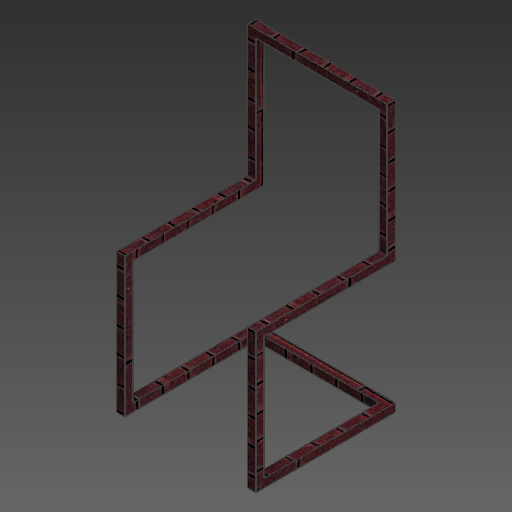
# Autodesk Inventor part: wednesday-23-09-2026
Saved by Autodesk Inventor 2026.1 (Build 301233020, 233B)
## iProperties
Created: 2026-09-23
Part Number: wednesday-23-09-2026
Material: Generic
Document SubType Name: Modeling
Designer: YmCris
Density: 1 g/cm^3
Appearance: Default
Author: YmCris
Autodesk Inventor part; units mm, degrees
ref_plane "YZ Plane" through (0, 0, 0) normal (1, 0, 0) x (0, 1, 0)
ref_plane "XZ Plane" through (0, 0, 0) normal (0, 1, 0) x (-1, 0, 0)
ref_plane "XY Plane" through (0, 0, 0) normal (0, 0, 1) x (1, 0, 0)
sketch "Sketch1" plane through (0, 0, 0) normal (0, 0, 1) x (1, 0, 0)
  line L0 (12.5, -12.5) -> (-12.5, -12.5)
  line L1 (-12.5, -12.5) -> (-12.5, 12.5)
  line L2 (-12.5, 12.5) -> (12.5, 12.5)
  line L3 (12.5, 12.5) -> (12.5, -12.5)
  dimension "d0" = 25
  dimension "d1" = 25
  constraints: 8 end point, 2 parallel, 1 horizontal, 1 perpendicular
  measures "d0" distance of L1.end L2.end
  measures "d1" distance of L0.end L1.end
sketch3d "3D Sketch1"
  line L0 (0, 0, 0) -> (0, 0, 400)
  line L1 (0, 0, 400) -> (0, 400, 400)
  line L2 (0, 400, 400) -> (0, 400, 0)
  line L3 (0, 400, 0) -> (0, 800, 0)
  line L4 (0, 800, 0) -> (400, 800, 0)
  line L5 (400, 800, 0) -> (400, 400, 0)
  line L6 (400, 400, 0) -> (400, 400, 400)
  line L7 (400, 400, 400) -> (400, 0, 400)
  line L8 (400, 0, 400) -> (400, 0, 0)
  line L9 (400, 0, 0) -> (0, 0, 0)
  dimension "d2" = 400
  dimension "d3" = 400
  dimension "d9" = 400
  dimension "d10" = 400
  dimension "d11" = 400
sweep "Sweep1" add profiles "Sketch1" path "3D Sketch1"
body "Solid1"
